MHCLid (Autodesk Fusion 360 design; units mm, degrees)
Autodesk Fusion 360 part; units mm, degrees
sketch "Sketch1" plane through (0, 0, 0) normal (0, 1, 0) x (1, 0, 0)
  line L0 (86.5, -62) -> (-86.5, -62)
  line L1 (-86.5, -62) -> (-86.5, 62)
  line L2 (-86.5, 62) -> (86.5, 62)
  line L3 (86.5, 62) -> (86.5, -62)
  line L4 (-86.5, 62) -> (-77.5, 62)
  line L5 (-77.5, 62) -> (-77.5, 53)
  line L6 (86.5, -62) -> (86.5, -53)
  line L7 (86.5, -53) -> (77.5, -53)
  line L8 (77.5, -53) -> (86.5, -62)
  line L9 (-86.5, 62) -> (-77.5, 53)
  circle A0 centre (-81, 56.5) radius 2.575
  circle A1 centre (81, -56.5) radius 2.575
  circle A2 centre (81, 56.5) radius 2.575
  circle A3 centre (-81, -56.5) radius 2.575
  line L10 (-77.5, 53) -> (77.5, 53)
  line L11 (77.5, 53) -> (77.5, -53)
  line L12 (77.5, -53) -> (-77.5, -53)
  line L13 (-77.5, -53) -> (-77.5, 53)
  line L14 (-77.5, -53) -> (-86.5, -53)
  line L15 (-77.5, -53) -> (-77.5, -62)
  line L16 (-77.5, 53) -> (-86.5, 53)
  line L17 (77.5, 53) -> (77.5, 62)
  line L18 (77.5, 53) -> (86.5, 53)
  line L19 (77.5, -53) -> (77.5, -62)
  line L20 (86.5, 62) -> (77.5, 53)
  line L21 (-86.5, -62) -> (-77.5, -53)
  line L22 (-81, 56.5) -> (81, 56.5)
  line L23 (81, 56.5) -> (81, -56.5)
  line L24 (81, -56.5) -> (-81, -56.5)
  line L25 (-81, -56.5) -> (-81, 56.5)
  dimension "d1" = 173
  dimension "d2" = 124
  dimension "d3" = 9
  constraint perpendicular L0 L1
  constraint parallel L0 L2
  constraint parallel L1 L3
  constraint horizontal L0
  constraint perpendicular L1 L4
  constraint perpendicular L4 L5
  constraint perpendicular L0 L6
  constraint perpendicular L6 L7
  constraint horizontal L10
  constraint vertical L11
  constraint horizontal L12
  constraint vertical L13
  constraint coincident L1 L14.end
  constraint perpendicular L1 L14
  constraint coincident L0 L15.end
  constraint perpendicular L0 L15
  constraint coincident L1 L16.end
  constraint perpendicular L1 L16
  constraint coincident L2 L17.end
  constraint perpendicular L2 L17
  constraint perpendicular L3 L18
  constraint coincident L0 L19.end
  constraint perpendicular L0 L19
  constraint parallel L20 L21
  constraint coincident A0.centre L22.start
  constraint coincident A2.centre L22.end
  constraint horizontal L22
  constraint coincident A1.centre L23.end
  constraint perpendicular L7 L23
  constraint coincident A3.centre L24.end
  constraint perpendicular L15 L24
  constraint perpendicular L22 L25
  measures "d1" distance of L1.end L2.end
  measures "d2" distance of L0.end L1.end
  measures "d3" distance of L1.end L4.end
extrude "Extrude1" add sketch "Sketch1" along normal blind 30
extrude "Extrude2" cut sketch "Sketch1" along normal blind 27 contours L12 L15 L19 L24 | L7 L11 L18 L23 | L10 L11 L12 L13 | L13 L14 L16 L25 | L5 L10 L17 L22
extrude "Extrude3" cut sketch "Sketch1" along normal blind 3 contours L8 A1 L24 | L8 A1 L23 | L8 A1 L24 | L8 A1 L23 | A3 L21 L24 | A3 L21 L25 | A3 L21 L24 | A2 L20 L22 | A2 L20 L23 | A2 L20 L23 | A3 L21 L25 | A2 L20 L22 | L9 A0 L25 | L9 A0 L22 | L9 A0 L22 | L9 A0 L25
sketch "Sketch2" plane through (0, 0, 0) normal (0, -1, 0) x (1, 0, 0)
  circle A0 centre (81, -56.5) radius 2.575
  circle A1 centre (-81, -56.5) radius 2.575
  circle A2 centre (81, 56.5) radius 2.575
  circle A3 centre (-81, 56.5) radius 2.575
  line L0 (77.5, 53) -> (81, 53)
  line L1 (81, -53) -> (77.5, -53)
  line L2 (77.5, -53) -> (77.5, -56.5)
  line L3 (-77.5, -56.5) -> (-77.5, -53)
  line L4 (-77.5, -53) -> (-81, -53)
  line L5 (-81, 53) -> (-77.5, 53)
  line L6 (-77.5, 53) -> (-77.5, 56.5)
  line L7 (77.5, 56.5) -> (77.5, 53)
  line L8 (86.5, 62) -> (-86.5, 62)
  line L9 (-86.5, 62) -> (-86.5, -62)
  line L10 (-86.5, -62) -> (86.5, -62)
  line L11 (86.5, -62) -> (86.5, 62)
  line L12 (77.5, -53) -> (-77.5, -53)
  line L13 (-77.5, -53) -> (-77.5, 53)
  line L14 (-77.5, 53) -> (77.5, 53)
  line L15 (77.5, 53) -> (77.5, -53)
  line L16 (77.5, -56.5) -> (-77.5, -56.5)
  line L17 (-81, -53) -> (-81, 53)
  line L18 (-77.5, 56.5) -> (77.5, 56.5)
  line L19 (81, 53) -> (81, -53)
  constraint horizontal L12
  constraint vertical L13
  constraint horizontal L14
  constraint vertical L15
  constraint coincident L5.end L6.start
  constraint coincident L1.end L2.start
sketch "Sketch3" plane through (0, 27, 0) normal (0, -1, 0) x (1, 0, 0)
  line L0 (81, 53) -> (77.5, 53)
  line L1 (77.5, 53) -> (77.5, 56.5)
  line L2 (-77.5, 56.5) -> (-77.5, 53)
  line L3 (-77.5, 53) -> (-81, 53)
  line L4 (-81, -53) -> (-77.5, -53)
  line L5 (-77.5, -53) -> (-77.5, -56.5)
  line L6 (77.5, -56.5) -> (77.5, -53)
  line L7 (77.5, -53) -> (81, -53)
  line L8 (-77.5, -56.5) -> (77.5, -56.5)
  line L9 (81, -53) -> (81, 53)
  line L10 (77.5, 56.5) -> (-77.5, 56.5)
  line L11 (-81, 53) -> (-81, -53)
extrude "Extrude4" add sketch "Sketch2" against normal blind 10 contours L6 L7 L14 L18 | L0 L1 L15 L19 | L4 L5 L13 L17 | L2 L3 L12 L16
fillet "Fillet1" radius 5 4 edges at (86.5, 15, 62) (-86.5, 15, 62) (-86.5, 15, -62) (86.5, 15, -62)
chamfer "Chamfer3" distance 3.5 distance2 7 4 edges at (77.5, 10, 0) (0, 10, 53) (0, 10, -53) (-77.5, 10, 0) measured on face at (78.6667, 10, 17.6667) measured on face at (25.8333, 10, 54.1667) measured on face at (-25.8333, 10, -54.1667) measured on face at (-78.6667, 10, -17.6667) tangent chain off
chamfer "Chamfer4" distance 3.5 angle 45 4 edges at (-77.5, 15, 53) (77.5, 15, 53) (77.5, 15, -53) (-77.5, 15, -53) tangent chain off
chamfer "Chamfer5" distance 0.5 angle 45 4 edges at (78.5993, 0, 57.4312) (78.5993, 0, -55.5688) (-83.4007, 0, -55.5688) (-83.4007, 0, 57.4312) tangent chain off
